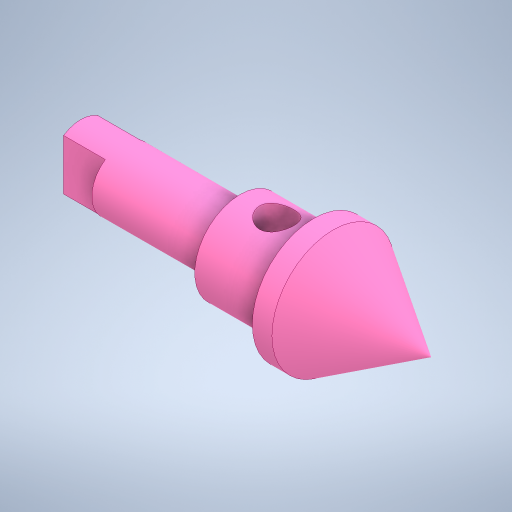
# Autodesk Inventor part: rotace
Saved by Autodesk Inventor 2024 (Build 280153000, 153)
## iProperties
Created: 2025-02-05
Part Number: rotace
Material: Ocel
Document SubType Name: Modeling
Designer: zak
Density: 7.85 g/cm^3
Appearance: Růžová
Mass: 767.233 g
Surface Area: 166.448 cm^2
Volume: 97.7367 cm^3
Author: zak
Autodesk Inventor part; units mm, degrees
ref_plane "YZ Plane" through (0, 0, 0) normal (1, 0, 0) x (0, 1, 0)
ref_plane "XY Plane" through (0, 0, 0) normal (0, 0, 1) x (1, 0, 0)
sketch "Náčrt2" plane through (0, 0, 0) normal (0, 0, 1) x (1, 0, 0)
  line L0 (0, 35) -> (0, -35) projected
  line L1 (-28.6, 0) -> (171.6, 0) projected
  line L2 (0, 12.5) -> (0, -12.5)
  line L3 (0, -12.5) -> (65, -12.5)
  line L4 (65, -12.5) -> (65, -18.5)
  line L5 (65, -18.5) -> (95, -18.5)
  line L6 (95, -18.5) -> (95, -25)
  line L7 (95, -25) -> (103, -25)
  line L8 (143, 0) -> (103, -25)
  line L9 (0, 12.5) -> (65, 12.5)
  line L10 (65, 12.5) -> (65, 18.5)
  line L11 (65, 18.5) -> (95, 18.5)
  line L12 (95, 18.5) -> (95, 25)
  line L13 (95, 25) -> (103, 25)
  line L14 (103, 25) -> (143, 0)
  point P0 (0, 0)
  point P1 (0, 0)
  point P2 (143, 0)
  dimension "d3" = 25
  dimension "d4" = 65
  dimension "d5" = 6
  dimension "d6" = 30
  dimension "d7" = 6.5
  dimension "d8" = 8
  dimension "d10" = 65
  dimension "d11" = 6
  dimension "d12" = 30
  dimension "d13" = 6.5
  dimension "d14" = 8
  dimension "d15" = 40
  dimension "d16" = 40
  dimension "d17" = 25
  dimension "d18" = 25
  dimension "d19" = 25
  dimension "d20" = 37
  dimension "d21" = 0
  constraints: 26 end point, 5 perpendicular, 1 horizontal
  measures "d3" distance of L2.start L2.end
  measures "d4" distance of L2.end L3.end
  measures "d5" distance of L3.end L4.end
  measures "d6" distance of L4.end L5.end
  measures "d7" distance of L5.end L6.end
  measures "d8" distance of L6.end L7.end
  measures "d10" distance of L2.start L9.end
  measures "d11" distance of L9.end L10.end
  measures "d12" distance of L10.end L11.end
  measures "d13" distance of L11.end L13.start
  measures "d14" distance of L13.start L13.end
  measures "d15" horizontal distance of L8.start L7.end
  measures "d16" horizontal distance of L13.end L8.start
  measures "d17" vertical distance of L8.start L7.end
  measures "d18" vertical distance of L13.end L8.start
  measures "d19" diameter of L9 L1
  measures "d20" diameter of L11 L1
  measures "d21" distance between parallel lines of L2 L0
revolve "Rotace1" add sketch "Náčrt2" angle 360 about axis through (0, 0, 0) along (1, 0, 0) contours L9 L10 L11 L12 L13 L14 L1 L0
sketch "Náčrt4" plane through (0, 0, 0) normal (1, 0, 0) x (0, 1, 0)
  line L0 (0, 17.5) -> (0, -17.5) projected
  line L1 (-17.5, 0) -> (17.5, 0) projected
  circle A0 centre (0, 0) radius 12.5 projected
  line L2 (10.3562, 7) -> (-10.3562, 7)
  line L3 (10.3562, -7) -> (-10.3562, -7)
  arc A1 (10.3562, 7) -> (-10.3562, 7) centre (0, 0) ccw
  arc A2 (-10.3562, -7) -> (10.3562, -7) centre (0, 0) ccw
  dimension "d30" = 7
  dimension "d31" = 7
  constraints: 8 point on circle, 4 end point, 2 centre point, 2 coincident, 2 horizontal
  measures "d30" distance between parallel lines of L1 L2
  measures "d31" distance between parallel lines of L3 L1
extrude "Vysunutí1" cut sketch "Náčrt4" along normal blind 17 contours A0 L2 L0 | L0 L2 A0
extrude "Vysunutí2" cut sketch "Náčrt4" along normal blind 17 contours L3 A0 L0 | L0 A0 L3
ref_plane "Pracovní rovina1" through (80, 18.5, 0) normal (0, 1, 0) x (-1, 0, 0)
sketch "Náčrt5" plane through (80, 18.5, 0) normal (0, 1, 0) x (-1, 0, 0)
  line L0 (108.6, 0) -> (-91.6, 0) projected
  line L1 (80, -35) -> (80, 35) projected
  line L2 (80, -35) -> (80, 35) projected
  line L3 (-91.6, 0) -> (108.6, 0) projected
  line L4 (15, 18.5) -> (15, -18.5) projected
  point P0 (80, 0)
  point P1 (0, 0)
  dimension "d36" = 15
  constraints: 1 point on line
  measures "d36" distance from line of L4 point (0, 0)
hole "Díra1" at (80, 18.5, 0) direction (0, -1, 0) diameter 14 end through all
